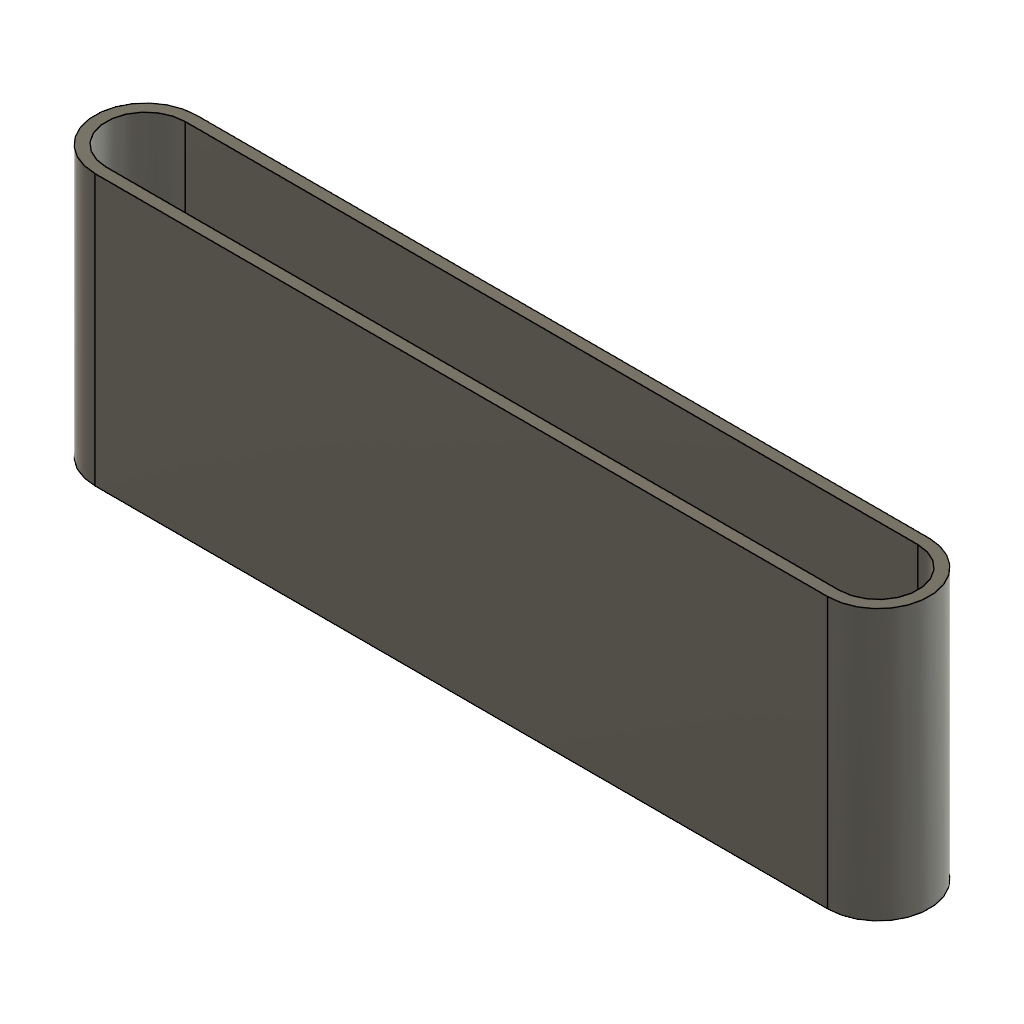
02-15_벨트 (Autodesk Fusion 360 design; units mm, degrees)
Autodesk Fusion 360 part; units mm, degrees
sketch "스케치1" plane through (0, 0, 0) normal (0, 1, 0) x (1, 0, 0)
  line L0 (-65, -9) -> (65, -9)
  arc A0 (65, -9) -> (65, 9) centre (65, 0) ccw
  line L1 (65, 9) -> (-65, 9)
  arc A1 (-65, 9) -> (-65, -9) centre (-65, 0) ccw
  line L2 (-65, 0) -> (65, 0) construction
  line L3 (-65, -7) -> (65, -7)
  arc A2 (65, -7) -> (65, 7) centre (65, 0) ccw
  line L4 (65, 7) -> (-65, 7)
  arc A3 (-65, 7) -> (-65, -7) centre (-65, 0) ccw
  line L5 (-65, 0) -> (65, 0) construction
  dimension "d1" = 18
  dimension "d2" = 14
  constraint tangent L0 A0
  constraint tangent A0 L1
  constraint parallel L0 L1
  constraint tangent L1 A1
  constraint tangent L0 A1
  constraint horizontal L2
  constraint midpoint origin L2
  constraint tangent L3 A2
  constraint tangent A2 L4
  constraint parallel L3 L4
  constraint tangent L4 A3
  constraint tangent L3 A3
  constraint coincident A0.centre L2.end
  constraint parallel L2 L5
  constraint coincident A1.centre L2.start
  measures "d1" diameter of A0
  measures "d2" diameter of A2
extrude "돌출1" add sketch "스케치1" along normal blind 48
